Autodesk Fusion 360 part; units mm, degrees
(part 7 of 8)
sketch "スケッチ3" plane through (0, 0, 0) normal (0, 1, 0) x (1, 0, 0)
  line L0 (0, -0.6) -> (0, -2)
  dimension "d5" = 1.4
  constraint vertical L0
  measures "d5" distance of L0.start L0.end
sketch "スケッチ4" plane through (0, 0, 0.6) normal (0, 0, 1) x (-1, 0, 0)
extrude "押し出し2" add sketch "スケッチ2" along normal blind 1.4 contours A1 | A3
chamfer "面取り1" distance 1.4 angle 45 1 edges at (3.0301, 1.1753, 2)

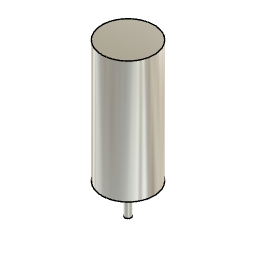
design "吸引モータ"
Autodesk Fusion 360 part; units mm, degrees
sketch "スケッチ1" plane through (0, 0, 0) normal (0, 0, 1) x (1, 0, 0)
  circle A0 centre (0, 0) radius 4.25
  dimension "d1" = 8.5
  constraint coincident A0.centre origin
  measures "d1" diameter of A0
extrude "押し出し1" add sketch "スケッチ1" along normal blind 20
sketch "スケッチ2" plane through (0, 0, 0) normal (0, 0, -1) x (1, 0, 0)
  circle A0 centre (0, 0) radius 4.25
  circle A1 centre (0, 0) radius 0.5
  dimension "d4" = 1
  constraint coincident A0.centre A1.centre
  measures "d4" diameter of A1
extrude "押し出し2" add sketch "スケッチ2" along normal blind 5 contours A1

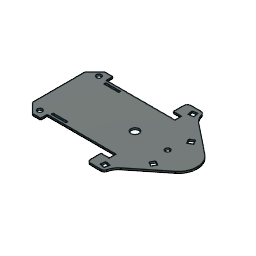
design "基板3"
Autodesk Fusion 360 part; units mm, degrees
sketch "スケッチ1" plane through (0, 0, 0) normal (0, 0, 1) x (1, 0, 0) in component "基板2 v12"
  line L0 (0, 0) -> (-42, 0)
  line L1 (-42, 0) -> (-42, 36.2)
  line L2 (-42, 36.2) -> (0, 36.2)
  line L3 (0, 36.2) -> (0, 0)
  dimension "d1" = 42
  dimension "d2" = 36.2
  constraint horizontal L0
  constraint vertical L1
  constraint horizontal L2
  constraint vertical L3
  constraint coincident L0.start L3.end
  measures "d1" distance of L0.start L0.end
  measures "d2" distance of L0.start L2.end
extrude "押し出し1" add sketch "スケッチ1" along normal blind 1 in component "基板2 v12"
sketch "スケッチ3" plane through (0, 0, 1) normal (0, 0, 1) x (-1, 0, 0) in component "基板2 v12"
  line L0 (0, -36.2) -> (42, -36.2)
  line L1 (42, -36.2) -> (42, 0)
  line L2 (42, 0) -> (0, 0)
  line L3 (42, -18.1) -> (42, 4)
  line L4 (42, 4) -> (47, 4)
  line L5 (47, 4) -> (47, -40.2)
  line L6 (47, -40.2) -> (42, -40.2)
  line L7 (42, -40.2) -> (42, 4)
  line L8 (0, 0) -> (0, -36.2)
  dimension "d7" = 22.1
  dimension "d8" = 44.2
  constraint midpoint L1 L3.start
  constraint perpendicular L2 L3
  constraint horizontal L4
  constraint vertical L5
  constraint horizontal L6
  constraint vertical L7
  measures "d7" distance of L3.start L3.end
  measures "d8" distance of L3.end L6.end
extrude "押し出し3" add sketch "スケッチ3" against normal blind 1 contours L1 L3 L4 L5 L6 L7 in component "基板2 v12"
sketch "スケッチ5" plane through (0, 0, 1) normal (0, 0, 1) x (-1, 0, 0) in component "基板2 v12"
  line L0 (0, -36.2) -> (42, -36.2)
  line L1 (42, -36.2) -> (42, -40.2)
  line L2 (42, -40.2) -> (47, -40.2)
  line L3 (47, -40.2) -> (47, 4)
  line L4 (47, 4) -> (42, 4)
  line L5 (42, 4) -> (42, 0)
  line L6 (42, 0) -> (0, 0)
  line L7 (0, 0) -> (0, -36.2)
  line L8 (21, -36.2) -> (21, 0)
  line L9 (21, -18.1) -> (51, -18.1)
  line L10 (51, -18.1) -> (51, -49)
  line L11 (47, -40.2) -> (58.1732, -40.2) construction
  line L12 (47, -40.2) -> (54.7082, -32.4918)
  line L13 (47, -40.2) -> (57.901, -40.2) construction
  line L14 (47, 4) -> (54.7082, -3.7082)
  line L15 (51, -18.1) -> (51, 12.8)
  dimension "d16" = 45
  constraint midpoint L0 L8.start
  constraint midpoint L6 L8.end
  constraint midpoint L8 L9.start
  constraint perpendicular L3 L9
  constraint perpendicular L9 L10
  constraint horizontal L11
  constraint coincident L2.end L3.start
  constraint horizontal L13
  constraint symmetric L10.start L9 L15.start
  constraint symmetric L9 L10.end L15.end
  constraint symmetric L9 L2.end L3.end
  constraint symmetric L9 L12.end L14.end
  measures "d16" angle of L12 L13
extrude "押し出し5" add sketch "スケッチ5" against normal blind 1 contours L3 L9 L10 L12 | L3 L9 L14 L15 in component "基板2 v12"
sketch "スケッチ6" plane through (0, 0, 1) normal (0, 0, 1) x (-1, 0, 0) in component "基板2 v12"
  line L0 (0, -36.2) -> (42, -36.2)
  line L1 (42, -36.2) -> (42, -40.2)
  line L2 (42, -40.2) -> (47, -40.2)
  line L3 (47, -40.2) -> (51, -36.2)
  line L4 (51, -36.2) -> (51, 0)
  line L5 (51, 0) -> (47, 4)
  line L6 (47, 4) -> (42, 4)
  line L7 (42, 4) -> (42, 0)
  line L8 (42, 0) -> (0, 0)
  line L9 (0, 0) -> (0, -36.2)
  line L10 (21, -36.2) -> (21, 0)
  line L11 (21, -18.1) -> (51, -18.1)
  line L12 (42, -36.2) -> (42, 0)
  line L13 (51, -18.1) -> (42, -18.1)
  line L14 (42, -36.2) -> (51, -36.2)
  circle A0 centre (46.5, -36.2) radius 1.5
  circle A1 centre (46.5, 0) radius 1.5
  dimension "d19" = 3
  constraint midpoint L0 L10.start
  constraint midpoint L8 L10.end
  constraint midpoint L10 L11.start
  constraint midpoint L4 L11.end
  constraint coincident L0.end L1.start
  constraint coincident L7.end L8.start
  constraint midpoint L12 L13.end
  constraint coincident L3.end L4.start
  constraint midpoint L14 A0.centre
  constraint symmetric L13 A0 A1
  measures "d19" diameter of A0
extrude "押し出し6" cut sketch "スケッチ6" against normal blind 9 contours L14 A0 | L14 A0 | A1 in component "基板2 v12"
sketch "スケッチ8" plane through (0, 0, 1) normal (0, 0, 1) x (-1, 0, 0) in component "基板2 v12"
  circle A0 centre (46.5, -36.2) radius 1.5
  circle A1 centre (46.5, 0) radius 1.5
  line L0 (0, -36.2) -> (42, -36.2)
  line L1 (42, -36.2) -> (42, -40.2)
  line L2 (42, -40.2) -> (47, -40.2)
  line L3 (47, -40.2) -> (51, -36.2)
  line L4 (51, -36.2) -> (51, 0)
  line L5 (51, 0) -> (47, 4)
  line L6 (47, 4) -> (42, 4)
  line L7 (42, 4) -> (42, 0)
  line L8 (42, 0) -> (0, 0)
  line L9 (0, 0) -> (0, -36.2)
  line L10 (0, -36.2) -> (0, -40.2)
  line L11 (0, -40.2) -> (-5, -40.2)
  line L12 (0, 0) -> (0, 4)
  line L13 (0, 4) -> (-5, 4)
  line L14 (-5, -40.2) -> (-5, 4)
  constraint coincident L0.start L9.end
  constraint perpendicular L2 L10
  constraint perpendicular L1 L11
  constraint coincident L8.end L9.start
  constraint perpendicular L8 L12
  constraint perpendicular L12 L13
  constraint perpendicular L13 L14
extrude "押し出し7" add sketch "スケッチ8" against normal blind 1 contours L9 L10 L11 L12 L13 L14 in component "基板2 v12"
sketch "スケッチ9" plane through (0, 0, 1) normal (0, 0, 1) x (-1, 0, 0) in component "基板2 v12"
  circle A0 centre (46.5, -36.2) radius 1.5
  circle A1 centre (46.5, 0) radius 1.5
  line L0 (0, -36.2) -> (42, -36.2)
  line L1 (42, -36.2) -> (42, -40.2)
  line L2 (42, -40.2) -> (47, -40.2)
  line L3 (47, -40.2) -> (51, -36.2)
  line L4 (51, -36.2) -> (51, 0)
  line L5 (51, 0) -> (47, 4)
  line L6 (47, 4) -> (42, 4)
  line L7 (42, 4) -> (42, 0)
  line L8 (42, 0) -> (0, 0)
  line L9 (0, 0) -> (0, 4)
  line L10 (0, 4) -> (-5, 4)
  line L11 (-5, 4) -> (-5, -40.2)
  line L12 (-5, -40.2) -> (0, -40.2)
  line L13 (0, -40.2) -> (0, -36.2)
  line L14 (-5, -18.1) -> (-25, -18.1)
  line L15 (-25, -18.1) -> (-25, -13.1)
  line L16 (-25, -18.1) -> (-25, -23.1)
  line L17 (-5, 4) -> (-25, -13.1)
  line L18 (-25, -23.1) -> (-5, -40.2)
  dimension "d26" = 20
  dimension "d39" = 5
  constraint midpoint L11 L14.start
  constraint perpendicular L11 L14
  constraint perpendicular L14 L15
  constraint symmetric L15.start L14 L16.start
  constraint symmetric L14 L15.end L16.end
  constraint coincident L10.end L11.start
  constraint coincident L11.end L12.start
  measures "d26" distance of L14.start L14.end
  measures "d39" distance of L14.end L15.end
extrude "押し出し8" add sketch "スケッチ9" against normal blind 1 contours L11 L14 L16 L18 | L11 L14 L15 L17 in component "基板2 v12"
sketch "スケッチ11" plane through (0, 0, 1) normal (0, 0, 1) x (-1, 0, 0) in component "基板2 v12"
  line L0 (-25, -13.1) -> (-25, -23.1)
  line L1 (-25, -23.1) -> (-5, -40.2)
  line L2 (-5, -40.2) -> (0, -40.2)
  line L3 (0, -40.2) -> (0, -36.2)
  line L4 (0, -36.2) -> (42, -36.2)
  line L5 (42, -36.2) -> (42, -40.2)
  line L6 (42, -40.2) -> (47, -40.2)
  line L7 (47, -40.2) -> (51, -36.2)
  line L8 (51, -36.2) -> (51, 0)
  line L9 (51, 0) -> (47, 4)
  line L10 (47, 4) -> (42, 4)
  line L11 (42, 4) -> (42, 0)
  line L12 (42, 0) -> (0, 0)
  line L13 (0, 0) -> (0, 4)
  line L14 (0, 4) -> (-5, 4)
  line L15 (-5, 4) -> (-25, -13.1)
  circle A0 centre (46.5, -36.2) radius 1.5
  circle A1 centre (46.5, 0) radius 1.5
  line L16 (46.5, 0) -> (46.5, -36.2)
  line L17 (46.5, -18.1) -> (-13.684, -18.1)
  circle A2 centre (-13.684, -18.1) radius 1.5
  dimension "d31" = 60.184
  dimension "d32" = 3
  constraint coincident A1.centre L16.start
  constraint coincident A0.centre L16.end
  constraint midpoint L16 L17.start
  constraint perpendicular L16 L17
  constraint coincident L17.end A2.centre
  measures "d31" distance of L17.start L17.end
  measures "d32" diameter of A2
extrude "押し出し9" cut sketch "スケッチ11" against normal blind 1 contours A2 in component "基板2 v12"
sketch "スケッチ12" plane through (0, 0, 1) normal (0, 0, 1) x (-1, 0, 0) in component "基板2 v12"
  circle A0 centre (-13.684, -18.1) radius 1.5
  line L0 (-25, -13.1) -> (-25, -23.1)
  line L1 (-25, -23.1) -> (-5, -40.2)
  line L2 (-5, -40.2) -> (0, -40.2)
  line L3 (0, -40.2) -> (0, -36.2)
  line L4 (0, -36.2) -> (42, -36.2)
  line L5 (42, -36.2) -> (42, -40.2)
  line L6 (42, -40.2) -> (47, -40.2)
  line L7 (47, -40.2) -> (51, -36.2)
  line L8 (51, -36.2) -> (51, 0)
  line L9 (51, 0) -> (47, 4)
  line L10 (47, 4) -> (42, 4)
  line L11 (42, 4) -> (42, 0)
  line L12 (42, 0) -> (0, 0)
  line L13 (0, 0) -> (0, 4)
  line L14 (0, 4) -> (-5, 4)
  line L15 (-5, 4) -> (-25, -13.1)
  circle A1 centre (46.5, -36.2) radius 1.5
  circle A2 centre (46.5, 0) radius 1.5
  line L16 (-13.684, -18.1) -> (6.316, -18.1)
  circle A3 centre (6.316, -18.1) radius 2.5
  dimension "d35" = 20
  dimension "d36" = 5
  constraint coincident A0.centre L16.start
  constraint parallel L6 L16
  constraint coincident L16.end A3.centre
  measures "d35" distance of A0.centre L16.end
  measures "d36" diameter of A3
extrude "押し出し10" cut sketch "スケッチ12" against normal blind 1 contours A3 in component "基板2 v12"
sketch "スケッチ17" plane through (0, 0, 1) normal (0, 0, 1) x (-1, 0, 0) in component "基板2 v12"
  circle A0 centre (6.316, -18.1) radius 2.5
  circle A1 centre (-13.684, -18.1) radius 1.5
  circle A2 centre (46.5, -36.2) radius 1.5
  circle A3 centre (46.5, 0) radius 1.5
  line L0 (47, 4) -> (42, 4)
  line L1 (42, 4) -> (42, 0)
  line L2 (42, 0) -> (0, 0)
  line L3 (0, 0) -> (0, 4)
  line L4 (0, 4) -> (-5, 4)
  line L5 (-5, 4) -> (-25, -13.1)
  line L6 (-25, -13.1) -> (-25, -23.1)
  line L7 (-25, -23.1) -> (-5, -40.2)
  line L8 (-5, -40.2) -> (0, -40.2)
  line L9 (0, -40.2) -> (0, -36.2)
  line L10 (0, -36.2) -> (42, -36.2)
  line L11 (42, -36.2) -> (42, -40.2)
  line L12 (42, -40.2) -> (47, -40.2)
  line L13 (47, -40.2) -> (51, -36.2)
  line L14 (51, -36.2) -> (51, 0)
  line L15 (51, 0) -> (47, 4)
  line L16 (0, -36.2) -> (0, -45)
  line L17 (0, -45) -> (-5, -45)
  line L18 (-5, -45) -> (-47.1614, -11.343)
  line L19 (-5, -45) -> (48.9479, -45) construction
  line L20 (-25, -18.1) -> (-38.697, -18.1)
  line L21 (-25, -29.0342) -> (-25, -18.1)
  line L22 (-5, 8.8) -> (-47.1614, -24.857)
  line L23 (-25, -7.1658) -> (-25, -18.1)
  line L24 (0, 8.8) -> (-5, 8.8)
  line L25 (0, 0) -> (0, 8.8)
  line L26 (-25, -18.1) -> (-31.8485, -18.1)
  line L27 (-31.8485, -18.1) -> (-31.8485, -23.5671)
  line L28 (-31.8485, -18.1) -> (-31.8485, -12.6329)
  line L29 (-5, -40.2) -> (-25, -23.1)
  line L30 (-25, -23.1) -> (-25, -13.1)
  line L31 (-25, -7.1658) -> (-25, -18.1)
  line L32 (-5, 4) -> (-25, -13.1)
  dimension "d66" = 141.4
  constraint coincident L9.end L10.start
  constraint perpendicular L10 L16
  constraint perpendicular L6 L17
  constraint horizontal L19
  constraint midpoint L6 L20.start
  constraint coincident L18 L20.end
  constraint perpendicular L6 L20
  constraint coincident L18 L21.start
  constraint perpendicular L20 L21
  constraint symmetric L9.end L20 L2.end
  constraint symmetric L16.end L20 L24.start
  constraint symmetric L17.end L20 L22.start
  constraint symmetric L18.end L20 L22.end
  constraint symmetric L21.end L20 L23.end
  constraint symmetric L20 L21.start L23.start
  constraint midpoint L20 L26.end
  constraint coincident L18 L27.end
  constraint perpendicular L20 L27
  constraint coincident L22 L28.end
  constraint perpendicular L20 L28
  constraint coincident L7.end L8.start
  constraint coincident L6.end L7.start
  constraint coincident L5.end L6.start
  constraint symmetric L20.start L26 L21.end
  constraint symmetric L21.start L26 L23.start
  constraint symmetric L26 L7.end L4.end
  constraint symmetric L26 L6.end L5.end
  measures "d66" angle of L18 L19
extrude "押し出し13" add sketch "スケッチ17" against normal blind 1 contours L4 L5 L22 L23 L24 L25 L31 L32 | L6 L20 L22 L23 L26 L28 L30 L31 | L6 L18 L20 L21 L26 L27 L30 | L7 L8 L16 L17 L18 L21 L29 in component "基板2 v12"
fillet "フィレット5" radius 1 4 edges at (5, 45, 0.5) (0, 45, 0.5) (0, -8.8, 0.5) (5, -8.8, 0.5) in component "基板2 v12"
fillet "フィレット7" radius 11.5 2 edges at (31.8485, 12.6329, 0.5) (31.8485, 23.5671, 0.5) in component "基板2 v12"
sketch "スケッチ13" plane through (0, 0, 1) normal (0, 0, 1) x (-1, 0, 0) in component "基板2 v12"
  line L0 (0, -44) -> (0, -36.2)
  line L1 (0, -36.2) -> (42, -36.2)
  line L2 (42, -36.2) -> (42, -40.2)
  line L3 (42, -40.2) -> (47, -40.2)
  line L4 (47, -40.2) -> (51, -36.2)
  line L5 (51, -36.2) -> (51, 0)
  line L6 (51, 0) -> (47, 4)
  line L7 (47, 4) -> (42, 4)
  line L8 (42, 4) -> (42, 0)
  line L9 (42, 0) -> (0, 0)
  circle A0 centre (6.316, -18.1) radius 2.5
  circle A1 centre (-13.684, -18.1) radius 1.5
  circle A2 centre (46.5, -36.2) radius 1.5
  circle A3 centre (46.5, 0) radius 1.5
  line L10 (6.316, -18.1) -> (-3.684, -18.1)
  line L11 (-3.684, -18.1) -> (-3.684, -16.6)
  line L12 (-3.684, -16.6) -> (-6.684, -16.6)
  line L13 (-6.684, -16.6) -> (-6.684, -19.6)
  line L14 (-6.684, -19.6) -> (-3.684, -19.6)
  line L15 (-3.684, -19.6) -> (-3.684, -18.1)
  line L16 (-0.5, -46.2) -> (-1.0209, -43.2456)
  line L17 (-0.5, -46.2) -> (-3.4, -46.2) construction
  line L18 (-1.0209, -43.2456) -> (-3.9754, -43.7665)
  line L19 (-3.9754, -43.7665) -> (-3.4544, -46.7209)
  line L20 (-3.4544, -46.7209) -> (-0.5, -46.2)
  line L21 (0, -36.2) -> (-17, -36.2)
  line L22 (-17, -36.2) -> (-17, -31.7)
  line L23 (-17, -31.7) -> (-14.4019, -30.2)
  line L24 (-14.4019, -30.2) -> (-15.9019, -27.6019)
  line L25 (-15.9019, -27.6019) -> (-18.5, -29.1019)
  line L26 (-17, -31.7) -> (-18.5, -29.1019)
  line L27 (-14.4019, -6) -> (-15.9019, -8.5981)
  line L28 (-15.9019, -8.5981) -> (-18.5, -7.0981)
  line L29 (-17, -4.5) -> (-18.5, -7.0981)
  line L30 (-17, -4.5) -> (-14.4019, -6)
  line L31 (-0.5, 10) -> (-1.0209, 7.0456)
  line L32 (-3.4544, 10.5209) -> (-0.5, 10)
  line L33 (-3.9754, 7.5665) -> (-3.4544, 10.5209)
  line L34 (-1.0209, 7.0456) -> (-3.9754, 7.5665)
  line L35 (0, -36.2) -> (0, -46.2)
  line L36 (0, -46.2) -> (-0.5, -46.2)
  arc A4 (-27.4386, -9.1125) -> (-27.4386, -27.0875) centre (-20.264, -18.1) ccw
  line L37 (-27.4386, -27.0875) -> (-5.2737, -44.7815)
  arc A5 (-5.2737, -44.7815) -> (-4.6498, -45) centre (-4.6498, -44) ccw
  line L38 (-4.6498, -45) -> (-1, -45)
  arc A6 (-1, -45) -> (0, -44) centre (-1, -44) ccw
  line L39 (0, 0) -> (0, 7.8)
  arc A7 (0, 7.8) -> (-1, 8.8) centre (-1, 7.8) ccw
  line L40 (-1, 8.8) -> (-4.6498, 8.8)
  arc A8 (-4.6498, 8.8) -> (-5.2737, 8.5815) centre (-4.6498, 7.8) ccw
  line L41 (-5.2737, 8.5815) -> (-27.4386, -9.1125)
  dimension "d42" = 10
  dimension "d43" = 1.5
  dimension "d44" = 3
  dimension "d45" = 3
  dimension "d46" = 3
  dimension "d49" = 100
  dimension "d50" = 3
  dimension "d51" = 3
  dimension "d52" = 3
  dimension "d53" = 120
  dimension "d54" = 3
  dimension "d55" = 3
  dimension "d56" = 3
  dimension "d57" = 4.5
  dimension "d58" = 17
  dimension "d75" = 10
  dimension "d76" = 0.5
  constraint coincident A0.centre L10.start
  constraint horizontal L10
  constraint perpendicular L10 L11
  constraint perpendicular L11 L12
  constraint perpendicular L12 L13
  constraint perpendicular L13 L14
  constraint horizontal L17
  constraint perpendicular L16 L18
  constraint perpendicular L18 L19
  constraint coincident L0.end L1.start
  constraint perpendicular L0 L21
  constraint perpendicular L21 L22
  constraint perpendicular L23 L24
  constraint perpendicular L24 L25
  constraint symmetric L10 L16.start L31.start
  constraint symmetric L10 L16.end L31.end
  constraint symmetric L10 L18.end L33.start
  constraint symmetric L10 L19.end L32.start
  constraint symmetric L10 L22.end L29.start
  constraint symmetric L10 L23.end L27.start
  constraint symmetric L10 L24.end L27.end
  constraint symmetric L10 L25.end L28.end
  constraint parallel L21 L36
  constraint parallel L0 L35
  measures "d42" distance of A0.centre L10.end
  measures "d43" distance of L10.end L11.end
  measures "d44" distance of L11.end L12.end
  measures "d45" distance of L12.end L13.end
  measures "d46" distance of L13.end L14.end
  measures "d49" angle of L16 L17
  measures "d50" distance of L16.start L16.end
  measures "d51" distance of L16.end L18.end
  measures "d52" distance of L18.end L19.end
  measures "d53" angle of L22 L23
  measures "d54" distance of L22.end L23.end
  measures "d55" distance of L23.end L24.end
  measures "d56" distance of L24.end L25.end
  measures "d57" distance of L21.end L22.end
  measures "d58" distance of L0.end L21.end
  measures "d75" distance of L0.end L35.end
  measures "d76" distance of L16.start L35.end
sketch "スケッチ14" plane through (0, 0, 1) normal (0, 0, 1) x (-1, 0, 0) in component "基板2 v12"
  line L0 (0, -44) -> (0, -36.2)
  line L1 (0, -36.2) -> (42, -36.2)
  line L2 (42, -36.2) -> (42, -40.2)
  line L3 (42, -40.2) -> (47, -40.2)
  line L4 (47, -40.2) -> (51, -36.2)
  line L5 (51, -36.2) -> (51, 0)
  line L6 (51, 0) -> (47, 4)
  line L7 (47, 4) -> (42, 4)
  line L8 (42, 4) -> (42, 0)
  line L9 (42, 0) -> (0, 0)
  circle A0 centre (6.316, -18.1) radius 2.5
  circle A1 centre (-13.684, -18.1) radius 1.5
  circle A2 centre (46.5, -36.2) radius 1.5
  circle A3 centre (46.5, 0) radius 1.5
  arc A4 (-27.4386, -9.1125) -> (-27.4386, -27.0875) centre (-20.264, -18.1) ccw
  line L10 (-27.4386, -27.0875) -> (-5.2737, -44.7815)
  arc A5 (-5.2737, -44.7815) -> (-4.6498, -45) centre (-4.6498, -44) ccw
  line L11 (-4.6498, -45) -> (-1, -45)
  arc A6 (-1, -45) -> (0, -44) centre (-1, -44) ccw
  line L12 (0, 0) -> (0, 7.8)
  arc A7 (0, 7.8) -> (-1, 8.8) centre (-1, 7.8) ccw
  line L13 (-1, 8.8) -> (-4.6498, 8.8)
  arc A8 (-4.6498, 8.8) -> (-5.2737, 8.5815) centre (-4.6498, 7.8) ccw
  line L14 (-5.2737, 8.5815) -> (-27.4386, -9.1125)
sketch "スケッチ15" plane through (0, 0, 1) normal (0, 0, 1) x (-1, 0, 0) in component "基板2 v12"
  line L0 (42, 0) -> (42, -1.5)
  line L1 (42, -1.5) -> (25.7723, -1.5)
  line L2 (42, -1.5) -> (40.924, -1.5)
  line L3 (40.924, -1.5) -> (40.924, -2.5)
  line L4 (40.924, -2.5) -> (31.924, -2.5)
  line L5 (31.924, -2.5) -> (31.924, -1.5)
  line L6 (42, 0) -> (42, -36.2)
  line L7 (42, -18.1) -> (30, -18.1)
  line L8 (31.924, -33.7) -> (31.924, -34.7)
  line L9 (42, -34.7) -> (40.924, -34.7)
  line L10 (40.924, -33.7) -> (31.924, -33.7)
  line L11 (42, -36.2) -> (42, -34.7)
  line L12 (40.924, -34.7) -> (40.924, -33.7)
  line L13 (42, -34.7) -> (25.7723, -34.7)
  dimension "d59" = 1.5
  dimension "d60" = 1.076
  dimension "d61" = 1
  dimension "d62" = 9
  constraint vertical L0
  constraint perpendicular L0 L1
  constraint perpendicular L0 L2
  constraint perpendicular L1 L3
  constraint perpendicular L3 L4
  constraint coincident L1 L5.end
  constraint perpendicular L1 L5
  constraint parallel L0 L6
  constraint midpoint L6 L7.start
  constraint perpendicular L6 L7
  constraint symmetric L0.start L7 L6.end
  constraint symmetric L0.end L7 L9.start
  constraint symmetric L1.end L7 L13.end
  constraint symmetric L2.end L7 L9.end
  constraint symmetric L3.end L7 L10.start
  constraint symmetric L4.end L7 L8.start
  constraint symmetric L5.end L7 L8.end
  measures "d59" distance of L0.start L0.end
  measures "d60" distance of L0.end L2.end
  measures "d61" distance of L2.end L3.end
  measures "d62" distance of L3.end L4.end
extrude "押し出し12" cut sketch "スケッチ15" against normal blind 1 in component "基板2 v12"
sketch "スケッチ1 (2)" plane through (0, 0, 1) normal (0, 0, 1) x (-1, 0, 0)
  line L0 (31.924, -2.5) -> (31.924, -1.5)
  line L1 (31.924, -1.5) -> (40.924, -1.5)
  line L2 (40.924, -1.5) -> (40.924, -2.5)
  line L3 (40.924, -2.5) -> (31.924, -2.5)
  line L4 (31.924, -33.7) -> (40.924, -33.7)
  line L5 (40.924, -33.7) -> (40.924, -34.7)
  line L6 (40.924, -34.7) -> (31.924, -34.7)
  line L7 (31.924, -34.7) -> (31.924, -33.7)
  arc A0 (-27.4386, -9.1125) -> (-27.4386, -27.0875) centre (-20.264, -18.1) ccw
  line L8 (-27.4386, -27.0875) -> (-5.2737, -44.7815)
  arc A1 (-5.2737, -44.7815) -> (-4.6498, -45) centre (-4.6498, -44) ccw
  line L9 (-4.6498, -45) -> (-1, -45)
  arc A2 (-1, -45) -> (0, -44) centre (-1, -44) ccw
  line L10 (0, -44) -> (0, -36.2)
  line L11 (0, -36.2) -> (42, -36.2)
  line L12 (42, -36.2) -> (42, -40.2)
  line L13 (42, -40.2) -> (47, -40.2)
  line L14 (47, -40.2) -> (51, -36.2)
  line L15 (51, -36.2) -> (51, 0)
  line L16 (51, 0) -> (47, 4)
  line L17 (47, 4) -> (42, 4)
  line L18 (42, 4) -> (42, 0)
  line L19 (42, 0) -> (0, 0)
  line L20 (0, 0) -> (0, 7.8)
  arc A3 (0, 7.8) -> (-1, 8.8) centre (-1, 7.8) ccw
  line L21 (-1, 8.8) -> (-4.6498, 8.8)
  arc A4 (-4.6498, 8.8) -> (-5.2737, 8.5815) centre (-4.6498, 7.8) ccw
  line L22 (-5.2737, 8.5815) -> (-27.4386, -9.1125)
  circle A5 centre (46.5, 0) radius 1.5
  circle A6 centre (46.5, -36.2) radius 1.5
  circle A7 centre (-13.684, -18.1) radius 1.5
  circle A8 centre (6.316, -18.1) radius 2.5
  line L23 (0, -36.2) -> (0, -40.2)
  line L24 (0, -40.2) -> (10, -40.2)
  line L25 (10, -40.2) -> (10, -50.2)
  line L26 (10, -50.2) -> (0, -50.2)
  line L27 (0, -50.2) -> (0, -40.2)
  line L28 (-5.2737, -44.7815) -> (-5.2737, -50.2)
  line L29 (-5.2737, -50.2) -> (0, -50.2)
  line L30 (-5.2737, -44.7815) -> (-5.2737, -48.7815)
  line L31 (-5.2737, -48.7815) -> (-6.5, -48.7815)
  line L32 (-6.5, -48.7815) -> (13.5, -48.7815)
  line L33 (-5.2737, -48.7815) -> (-16.3562, -35.9345)
  line L34 (-13.684, -18.1) -> (6.316, -18.1)
  arc A9 (-4.6498, 8.8) -> (-5.2737, 8.5815) centre (-4.6498, 7.8) ccw
  line L35 (0, 7.8) -> (0, 0)
  line L36 (0, 4) -> (10, 4)
  line L37 (-5.2737, 14) -> (0, 14)
  line L38 (10, 4) -> (10, 14)
  line L39 (10, 14) -> (0, 14)
  line L40 (-5.2737, 8.5815) -> (-5.2737, 12.5815)
  line L41 (0, 0) -> (0, 4)
  line L42 (-6.5, 12.5815) -> (13.5, 12.5815)
  line L43 (-5.2737, 12.5815) -> (-6.5, 12.5815)
  line L44 (0, 14) -> (0, 4)
  line L45 (-5.2737, 8.5815) -> (-5.2737, 14)
  line L46 (-5.2737, 12.5815) -> (-16.3562, -0.2655)
  line L47 (-0.7123, 8.7961) -> (-1, 8.8)
  line L48 (-1.0209, 7.0456) -> (-0.7123, 8.7961)
  line L49 (-1, 8.8) -> (-1.3466, 7.103)
  line L50 (-1.3466, 7.103) -> (-1.0209, 7.0456)
  line L51 (-4.6498, 8.8) -> (-1, 8.8)
  arc A10 (0, 7.8) -> (-1, 8.8) centre (-1, 7.8) ccw
  line L52 (0, -40.2) -> (5, -40.2)
  line L53 (5, -40.2) -> (5, -50.2)
  line L54 (0, 4) -> (5, 4)
  line L55 (5, 14) -> (5, 4)
  dimension "d5" = 4
  dimension "d6" = 10
  dimension "d11" = 4
  constraint coincident L10.end L11.start
  constraint perpendicular L11 L23
  constraint perpendicular L10 L24
  constraint perpendicular L24 L25
  constraint perpendicular L25 L26
  constraint perpendicular L24 L27
  constraint coincident L8.end A1.start
  constraint perpendicular L26 L28
  constraint perpendicular L27 L29
  constraint parallel L28 L30
  constraint perpendicular L30 L31
  constraint perpendicular L25 L32
  constraint midpoint L8 L33.end
  constraint coincident A7.centre L34.start
  constraint coincident A8.centre L34.end
  constraint symmetric L9.end L34 A3.end
  constraint symmetric L8.end L34 A4.end
  constraint symmetric A1.end L34 L21.end
  constraint symmetric A1 L34 A9
  constraint symmetric A2.end L34 L20.end
  constraint symmetric A2 L34 A10
  constraint symmetric L10.end L34 L19.end
  constraint symmetric L23.end L34 L36.start
  constraint symmetric L24.end L34 L36.end
  constraint symmetric L25.end L34 L38.end
  constraint symmetric L26.end L34 L37.end
  constraint symmetric L28.end L34 L37.start
  constraint symmetric L30.end L34 L40.end
  constraint symmetric L31.end L34 L42.start
  constraint symmetric L32.end L34 L42.end
  constraint symmetric L33.end L34 L46.end
  constraint midpoint L24 L52.end
  constraint midpoint L26 L53.end
  constraint midpoint L36 L54.end
  constraint midpoint L39 L55.start
  measures "d5" distance of L10.end L23.end
  measures "d6" distance of L24.end L25.end
  measures "d11" distance of L8.end L30.end
extrude "押し出し14" add sketch "スケッチ1 (2)" against normal blind 1 contours A3 L47 L48 A10 | A3 L21 A4 A9 L40 L42 L44 L45 L47 L48 L51 A10 | A1 L9 A2 L27 L28 L30 L32 | L20 L35 L36 L42 L44 L54 L55 | L10 L24 L27 L32 L52 L53 in component "基板2 v12"
fillet "フィレット8" radius 9.5 2 edges at (5.2737, 44.7815, 0.5) (5.2737, -8.5815, 0.5) in component "基板2 v12"
extrude "押し出し15" cut sketch "スケッチ13" against normal blind 8 contours L16 L18 L19 L38 A6 | L16 L19 L20 L38 A6 | L31 L33 L34 A7 L40 | L31 L32 L33 A7 L40 | L23 L24 L25 L26 | L27 L28 L29 L30 in component "基板2 v12"
fillet "フィレット9" radius 2 4 edges at (5.2737, 48.7815, 0.5) (5.2737, -12.5815, 0.5) (-5, -12.5815, 0.5) (-5, 48.7815, 0.5) in component "基板2 v12"
sketch "スケッチ2" plane through (0, 0, 1) normal (0, 0, 1) x (-1, 0, 0)
  line L0 (-18.5, -29.1019) -> (-15.9019, -27.6019)
  line L1 (-15.9019, -27.6019) -> (-14.4019, -30.2)
  line L2 (-14.4019, -30.2) -> (-17, -31.7)
  line L3 (-17, -31.7) -> (-18.5, -29.1019)
  line L4 (-15.9019, -8.5981) -> (-18.5, -7.0981)
  line L5 (-18.5, -7.0981) -> (-17, -4.5)
  line L6 (-17, -4.5) -> (-14.4019, -6)
  line L7 (-14.4019, -6) -> (-15.9019, -8.5981)
  line L8 (-1.0209, -43.2456) -> (-0.5, -46.2)
  line L9 (-0.5, -46.2) -> (-3.4544, -46.7209)
  line L10 (-3.4544, -46.7209) -> (-3.9754, -43.7665)
  line L11 (-3.9754, -43.7665) -> (-1.0209, -43.2456)
  line L12 (-3.4544, 10.5209) -> (-0.5, 10)
  line L13 (-0.5, 10) -> (-1.0209, 7.0456)
  line L14 (-1.0209, 7.0456) -> (-3.9754, 7.5665)
  line L15 (-3.9754, 7.5665) -> (-3.4544, 10.5209)
  line L16 (31.924, -2.5) -> (31.924, -1.5)
  line L17 (31.924, -1.5) -> (40.924, -1.5)
  line L18 (40.924, -1.5) -> (40.924, -2.5)
  line L19 (40.924, -2.5) -> (31.924, -2.5)
  line L20 (31.924, -33.7) -> (40.924, -33.7)
  line L21 (40.924, -33.7) -> (40.924, -34.7)
  line L22 (40.924, -34.7) -> (31.924, -34.7)
  line L23 (31.924, -34.7) -> (31.924, -33.7)
  arc A0 (3, -48.7815) -> (5, -46.7815) centre (3, -46.7815) ccw
  line L24 (5, -46.7815) -> (5, -40.2)
  line L25 (5, -40.2) -> (0, -40.2)
  line L26 (0, -40.2) -> (0, -36.2)
  line L27 (0, -36.2) -> (42, -36.2)
  line L28 (42, -36.2) -> (42, -40.2)
  line L29 (42, -40.2) -> (47, -40.2)
  line L30 (47, -40.2) -> (51, -36.2)
  line L31 (51, -36.2) -> (51, 0)
  line L32 (51, 0) -> (47, 4)
  line L33 (47, 4) -> (42, 4)
  line L34 (42, 4) -> (42, 0)
  line L35 (42, 0) -> (0, 0)
  line L36 (0, 0) -> (0, 4)
  line L37 (0, 4) -> (5, 4)
  line L38 (5, 4) -> (5, 10.5815)
  arc A1 (5, 10.5815) -> (3, 12.5815) centre (3, 10.5815) ccw
  line L39 (3, 12.5815) -> (-3.5502, 12.5815)
  arc A2 (-3.5502, 12.5815) -> (-5.499, 11.0313) centre (-3.5502, 10.5815) ccw
  arc A3 (-8.8287, 5.7436) -> (-5.499, 11.0313) centre (-14.7556, 13.168) ccw
  line L40 (-8.8287, 5.7436) -> (-27.4386, -9.1125)
  arc A4 (-27.4386, -9.1125) -> (-27.4386, -27.0875) centre (-20.264, -18.1) ccw
  line L41 (-27.4386, -27.0875) -> (-8.8287, -41.9436)
  arc A5 (-5.499, -47.2313) -> (-8.8287, -41.9436) centre (-14.7556, -49.368) ccw
  arc A6 (-5.499, -47.2313) -> (-3.5502, -48.7815) centre (-3.5502, -46.7815) ccw
  line L42 (-3.5502, -48.7815) -> (3, -48.7815)
  circle A7 centre (46.5, 0) radius 1.5
  circle A8 centre (46.5, -36.2) radius 1.5
  circle A9 centre (-13.684, -18.1) radius 1.5
  circle A10 centre (6.316, -18.1) radius 2.5
  line L43 (51, -18.1) -> (53, -18.1)
  line L44 (51, 0) -> (54, -3)
  line L45 (53, -18.1) -> (53, -2)
  line L46 (51, -36.2) -> (56.6028, -30.5972)
  line L47 (53, -18.1) -> (53, -35)
  constraint midpoint L31 L43.start
  constraint perpendicular L31 L43
  constraint coincident L31.end L32.start
  constraint parallel L32 L44
  constraint coincident L44 L45.end
  constraint perpendicular L43 L45
  constraint coincident L30.end L31.start
  constraint perpendicular L44 L46
  constraint perpendicular L43 L47
extrude "押し出し16" add sketch "スケッチ2" against normal blind 1 contours L31 L43 L46 L47 | L31 L43 L44 L45 in component "基板2 v12"
fillet "フィレット10" radius 1 4 edges at (-47, -4, 0.5) (-53, 2, 0.5) (-47, 40.2, 0.5) (-53, 34.2, 0.5) in component "基板2 v12"
sketch "スケッチ3 (2)" plane through (0, 0, 1) normal (0, 0, 1) x (-1, 0, 0)
  arc A0 (52.7071, -34.4929) -> (53, -33.7858) centre (52, -33.7858) ccw
  line L0 (53, -33.7858) -> (53, -2.4142)
  arc A1 (53, -2.4142) -> (52.7071, -1.7071) centre (52, -2.4142) ccw
  line L1 (52.7071, -1.7071) -> (51, 0)
  line L2 (51, 0) -> (47.2929, 3.7071)
  arc A2 (47.2929, 3.7071) -> (46.5858, 4) centre (46.5858, 3) ccw
  line L3 (46.5858, 4) -> (42, 4)
  line L4 (42, 4) -> (42, 0)
  line L5 (42, 0) -> (0, 0)
  line L6 (0, 0) -> (0, 4)
  line L7 (0, 4) -> (5, 4)
  line L8 (5, 4) -> (5, 10.5815)
  arc A3 (5, 10.5815) -> (3, 12.5815) centre (3, 10.5815) ccw
  line L9 (3, 12.5815) -> (-3.5502, 12.5815)
  arc A4 (-3.5502, 12.5815) -> (-5.499, 11.0313) centre (-3.5502, 10.5815) ccw
  arc A5 (-8.8287, 5.7436) -> (-5.499, 11.0313) centre (-14.7556, 13.168) ccw
  line L10 (-8.8287, 5.7436) -> (-27.4386, -9.1125)
  arc A6 (-27.4386, -9.1125) -> (-27.4386, -27.0875) centre (-20.264, -18.1) ccw
  line L11 (-27.4386, -27.0875) -> (-8.8287, -41.9436)
  arc A7 (-5.499, -47.2313) -> (-8.8287, -41.9436) centre (-14.7556, -49.368) ccw
  arc A8 (-5.499, -47.2313) -> (-3.5502, -48.7815) centre (-3.5502, -46.7815) ccw
  line L12 (-3.5502, -48.7815) -> (3, -48.7815)
  arc A9 (3, -48.7815) -> (5, -46.7815) centre (3, -46.7815) ccw
  line L13 (5, -46.7815) -> (5, -40.2)
  line L14 (5, -40.2) -> (0, -40.2)
  line L15 (0, -40.2) -> (0, -36.2)
  line L16 (0, -36.2) -> (42, -36.2)
  line L17 (42, -36.2) -> (42, -40.2)
  line L18 (42, -40.2) -> (46.5858, -40.2)
  arc A10 (46.5858, -40.2) -> (47.2929, -39.9071) centre (46.5858, -39.2) ccw
  line L19 (47.2929, -39.9071) -> (51, -36.2)
  line L20 (51, -36.2) -> (52.7071, -34.4929)
  circle A11 centre (6.316, -18.1) radius 2.5
  circle A12 centre (-13.684, -18.1) radius 1.5
  circle A13 centre (46.5, -36.2) radius 1.5
  circle A14 centre (46.5, 0) radius 1.5
  line L21 (31.924, -33.7) -> (40.924, -33.7)
  line L22 (40.924, -33.7) -> (40.924, -34.7)
  line L23 (40.924, -34.7) -> (31.924, -34.7)
  line L24 (31.924, -34.7) -> (31.924, -33.7)
  line L25 (31.924, -2.5) -> (31.924, -1.5)
  line L26 (31.924, -1.5) -> (40.924, -1.5)
  line L27 (40.924, -1.5) -> (40.924, -2.5)
  line L28 (40.924, -2.5) -> (31.924, -2.5)
  line L29 (-3.4544, 10.5209) -> (-0.5, 10)
  line L30 (-0.5, 10) -> (-1.0209, 7.0456)
  line L31 (-1.0209, 7.0456) -> (-3.9754, 7.5665)
  line L32 (-3.9754, 7.5665) -> (-3.4544, 10.5209)
  line L33 (-1.0209, -43.2456) -> (-0.5, -46.2)
  line L34 (-0.5, -46.2) -> (-3.4544, -46.7209)
  line L35 (-3.4544, -46.7209) -> (-3.9754, -43.7665)
  line L36 (-3.9754, -43.7665) -> (-1.0209, -43.2456)
  line L37 (-15.9019, -8.5981) -> (-18.5, -7.0981)
  line L38 (-18.5, -7.0981) -> (-17, -4.5)
  line L39 (-17, -4.5) -> (-14.4019, -6)
  line L40 (-14.4019, -6) -> (-15.9019, -8.5981)
  line L41 (-18.5, -29.1019) -> (-15.9019, -27.6019)
  line L42 (-15.9019, -27.6019) -> (-14.4019, -30.2)
  line L43 (-14.4019, -30.2) -> (-17, -31.7)
  line L44 (-17, -31.7) -> (-18.5, -29.1019)
component "基板2 v12" placed x (1, 0, 0) y (0, 1, 0) z (0, 0, 1) at (0, 0, 0)
equation "d7 = ( 44.2 / 2 ) * 1 mm"
equation "d53 = 90 deg + 30 deg"

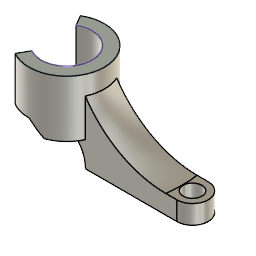
design "吸引モーター抑え"
Autodesk Fusion 360 part; units mm, degrees
sketch "スケッチ1" plane through (0, 0, 0) normal (0, 0, 1) x (1, 0, 0)
  circle A0 centre (0, 0) radius 4.25
  line L0 (0, 0) -> (20, 0)
  circle A1 centre (20, 0) radius 1.5
  circle A2 centre (20, 0) radius 2.5
  line L1 (20, 0) -> (20, 2.5)
  line L2 (20, 2.5) -> (3.4369, 2.5)
  line L3 (20, -2.5) -> (3.4369, -2.5)
  line L4 (3.4369, 2.5) -> (3.4369, -2.5)
  circle A3 centre (0, 0) radius 6
  line L5 (0, 0) -> (2.0521, 5.6382)
  line L6 (0, 0) -> (6, 0) construction
  line L7 (0, 0) -> (2.0521, -5.6382)
  dimension "d1" = 8.5
  dimension "d2" = 20
  dimension "d3" = 3
  dimension "d4" = 5
  dimension "d5" = 70
  constraint coincident A0.centre L0.start
  constraint horizontal L0
  constraint coincident L0.end A1.centre
  constraint concentric A1 A2
  constraint coincident A2 L1.end
  constraint perpendicular L0 L1
  constraint coincident A0 L2.end
  constraint perpendicular L1 L2
  constraint coincident A2 L3.start
  constraint coincident A0 L3.end
  constraint tangent A2 L3
  constraint parallel L2 L3
  constraint concentric A0 A3
  constraint horizontal L6
  constraint symmetric L0 A0.centre A3.centre
  constraint symmetric L0 L5.end L7.end
  measures "d1" diameter of A0
  measures "d2" distance of A0.centre L0.end
  measures "d3" diameter of A1
  measures "d4" diameter of A2
  measures "d5" angle of L5 L6
extrude "押し出し1" add sketch "スケッチ1" along normal blind 2 contours A0 L0 L3 A3 | A0 L0 L2 A3 | A0 L2 A3 L5 | A0 L3 A3 L7 | L0 A2 L2 A3 | L0 A2 L3 A3 | L0 A1 A2 L1 | L0 A1 A2 L1
sketch "スケッチ2" plane through (0, 0, 2) normal (0, 0, 1) x (-1, 0, 0)
  circle A0 centre (-20, 0) radius 1.5
  line L0 (-1.4536, 3.9937) -> (-2.0521, 5.6382)
  arc A1 (-2.0521, 5.6382) -> (-5.4544, 2.5) centre (0, 0) ccw
  line L1 (-5.4544, 2.5) -> (-20, 2.5)
  arc A2 (-20, 2.5) -> (-20, -2.5) centre (-20, 0) ccw
  line L2 (-20, -2.5) -> (-5.4544, -2.5)
  arc A3 (-5.4544, -2.5) -> (-2.0521, -5.6382) centre (0, 0) ccw
  line L3 (-2.0521, -5.6382) -> (-1.4536, -3.9937)
  arc A4 (-1.4536, 3.9937) -> (-1.4536, -3.9937) centre (0, 0) ccw
  circle A5 centre (0, 0) radius 4.25
  circle A6 centre (0, 0) radius 6
  constraint coincident A1.centre A3.centre
  constraint concentric A5 A6
  constraint coincident L2.end A6
extrude "押し出し2" add sketch "スケッチ2" along normal blind 7 contours L0 A1 A3 L3 A4 A5 A6
fillet "フィレット1" radius 14.5 1 edges at (6, 0, 2)
sketch "スケッチ3" plane through (0, 0, 0) normal (0, 0, -1) x (1, 0, 0)
  circle A0 centre (20, 0) radius 1.5
  line L0 (2.0521, 5.6382) -> (1.4536, 3.9937)
  arc A1 (1.4536, -3.9937) -> (1.4536, 3.9937) centre (0, 0) ccw
  line L1 (1.4536, -3.9937) -> (2.0521, -5.6382)
  arc A2 (2.0521, -5.6382) -> (5.4544, -2.5) centre (0, 0) ccw
  line L2 (5.4544, -2.5) -> (20, -2.5)
  arc A3 (20, -2.5) -> (20, 2.5) centre (20, 0) ccw
  line L3 (20, 2.5) -> (5.4544, 2.5)
  arc A4 (5.4544, 2.5) -> (2.0521, 5.6382) centre (0, 0) ccw
  circle A5 centre (0, 0) radius 6
  constraint coincident A1.centre A2.centre
extrude "押し出し3" cut sketch "スケッチ3" against normal blind 4 contours L0 A1 L1 A2 A4 A5
extrude "押し出し4" add 1 faces at (14.7849, 2.0068, 0) along direction (0, 0, -1) blind 1
extrude "押し出し5" add 2 faces at (5.3925, 0.3873, 4) (5.3925, 0.3873, 4) along direction (0, 0, -1) blind 1
fillet "フィレット3" radius 5 1 edges at (6, 0, 3)
sketch "スケッチ4" plane through (0, 0, 9) normal (0, 0, 1) x (-1, 0, 0)
  line L0 (-1.4536, 3.9937) -> (-2.0521, 5.6382)
  arc A0 (-2.0521, 5.6382) -> (-5.4544, 2.5) centre (0, 0) ccw
  arc A1 (-5.4544, 2.5) -> (-5.4544, -2.5) centre (0, 0) ccw
  arc A2 (-5.4544, -2.5) -> (-2.0521, -5.6382) centre (0, 0) ccw
  line L1 (-2.0521, -5.6382) -> (-1.4536, -3.9937)
  arc A3 (-1.4536, 3.9937) -> (-1.4536, -3.9937) centre (0, 0) ccw
extrude "押し出し6" add sketch "スケッチ4" along normal blind 3
sketch "スケッチ5" plane through (0, 0, 12) normal (0, 0, 1) x (-1, 0, 0)
  arc A0 (-2.0521, 5.6382) -> (-2.0521, -5.6382) centre (0, 0) ccw
  line L0 (-2.0521, -5.6382) -> (-1.4536, -3.9937)
  arc A1 (-1.4536, 3.9937) -> (-1.4536, -3.9937) centre (0, 0) ccw
  line L1 (-1.4536, 3.9937) -> (-2.0521, 5.6382)
  circle A2 centre (0, 0) radius 4.25
  circle A3 centre (0, 0) radius 6
  line L2 (0, 0) -> (3, 5.1962)
  line L3 (0, 0) -> (6, 0) construction
  line L4 (0, 0) -> (6, 0)
  line L5 (0, 0) -> (3, -5.1962)
  circle A4 centre (0, 0) radius 4.05
  dimension "d24" = 60
  dimension "d28" = 8.1
  constraint concentric A0 A2
  constraint coincident L0.end A2
  constraint concentric A0 A3
  constraint coincident A0.end A3
  constraint horizontal L3
  constraint coincident A0.centre A1.centre
  constraint symmetric A0.centre L4 A1.centre
  constraint symmetric L2.end L4 L5.end
  constraint concentric A2 A4
  measures "d24" angle of L2 L3
  measures "d28" diameter of A4
extrude "押し出し7" add sketch "スケッチ5" against normal blind 7 contours L1 A2 A3 L2 | L0 A2 A3 L5 | A1 A2 L2 L5 A4
chamfer "面取り1" distance 2 angle 45 2 edges at (1.7529, -4.8159, 5) (1.7529, 4.8159, 5)
sketch "スケッチ6" plane through (0, 0, 12) normal (0, 0, 1) x (-1, 0, 0)
  arc A0 (3, 5.1962) -> (3, -5.1962) centre (0, 0) ccw
  line L0 (3, -5.1962) -> (2.025, -3.5074)
  line L1 (2.025, 3.5074) -> (3, 5.1962)
  arc A1 (2.025, 3.5074) -> (2.025, -3.5074) centre (0, 0) ccw
equation "d1 = ( 4.25 * 2 ) * 1 mm"

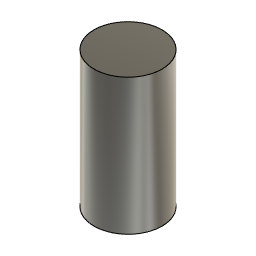
design "3*6平行ピン"
Autodesk Fusion 360 part; units mm, degrees
sketch "スケッチ1" plane through (0, 0, 0) normal (0, 0, 1) x (1, 0, 0)
  circle A0 centre (0, 0) radius 1.5
  dimension "d1" = 3
  constraint coincident A0.centre origin
  measures "d1" diameter of A0
extrude "押し出し1" add sketch "スケッチ1" along normal blind 6

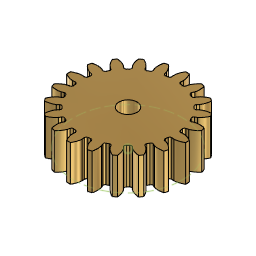
design "歯車M0.3T20"
description: Spur Gear; Module: 0.300000; Num Teeth: 20; Pressure Angle: 20.000000; Backlash: 0.00 mm
Autodesk Fusion 360 part; units mm, degrees
sketch "スケッチ1" plane through (0, 0, 0) normal (0, 0, 1) x (1, 0, 0) in component "Spur Gear (20 teeth)"
  circle A0 centre (0, 0) radius 2.5892
  circle A1 centre (0, 0) radius 0.75
extrude "押し出し1" add sketch "スケッチ1" along normal blind 2 in component "Spur Gear (20 teeth)"
sketch "スケッチ2" plane through (0, 0, 0) normal (0, 0, 1) x (1, 0, 0) in component "Spur Gear (20 teeth)"
  spline S0 degree 3 poles (2.8068, -0.263) (2.8248, -0.2628) (2.8611, -0.2624) (2.9154, -0.2535) (2.9701, -0.2415) (3.0249, -0.2258) (3.0798, -0.2071) (3.1347, -0.1854) (3.1895, -0.161) (3.2443, -0.1341) (3.2802, -0.1142) (3.2984, -0.1042) knots 0 0 0 0 0.005388 0.010882 0.016478 0.022176 0.027974 0.033875 0.039876 0.045979 0.052183 0.052183 0.052183 0.052183
  spline S1 degree 3 poles (2.8068, 0.263) (2.8248, 0.2628) (2.8611, 0.2624) (2.9154, 0.2535) (2.9701, 0.2415) (3.0249, 0.2258) (3.0798, 0.2071) (3.1347, 0.1854) (3.1895, 0.161) (3.2443, 0.1341) (3.2802, 0.1142) (3.2984, 0.1042) knots 0 0 0 0 0.005388 0.010882 0.016478 0.022176 0.027974 0.033875 0.039876 0.045979 0.052183 0.052183 0.052183 0.052183
  arc A0 (3.2984, -0.1042) -> (3.2984, 0.1042) centre (0, 0) ccw
  line L0 (2.5679, -0.2416) -> (2.8068, -0.263)
  line L1 (2.5679, 0.2416) -> (2.8068, 0.263)
  line L2 (2.5679, -0.2416) -> (2.5679, 0.2416)
  point P0 (2.8606, -0.2611)
  point P1 (2.915, -0.2531)
  point P2 (2.9696, -0.241)
  point P3 (3.0244, -0.2254)
  point P4 (3.0793, -0.2067)
  point P5 (3.1342, -0.1851)
  point P6 (3.1891, -0.1608)
  point P7 (3.2438, -0.1338)
  point P8 (2.8606, 0.2611)
  point P9 (2.915, 0.2531)
  point P10 (2.9696, 0.241)
  point P11 (3.0244, 0.2254)
  point P12 (3.0793, 0.2067)
  point P13 (3.1342, 0.1851)
  point P14 (3.1891, 0.1608)
  point P15 (3.2438, 0.1338)
extrude "押し出し2" add sketch "スケッチ2" along normal blind 2 in component "Spur Gear (20 teeth)"
fillet "フィレット1" radius 0.1 2 edges at (2.5778, -0.2425, 1) (2.5778, 0.2425, 1) in component "Spur Gear (20 teeth)"
pattern_circular "C パターン1" count 20 over 360 about axis through (0, 0, 0) along (0, 0, 1) of "押し出し2", "フィレット1" in component "Spur Gear (20 teeth)"
sketch "スケッチ3" plane through (0, 0, 0) normal (0, 0, 1) x (1, 0, 0) in component "Spur Gear (20 teeth)"
  circle A0 centre (0, 0) radius 3 construction